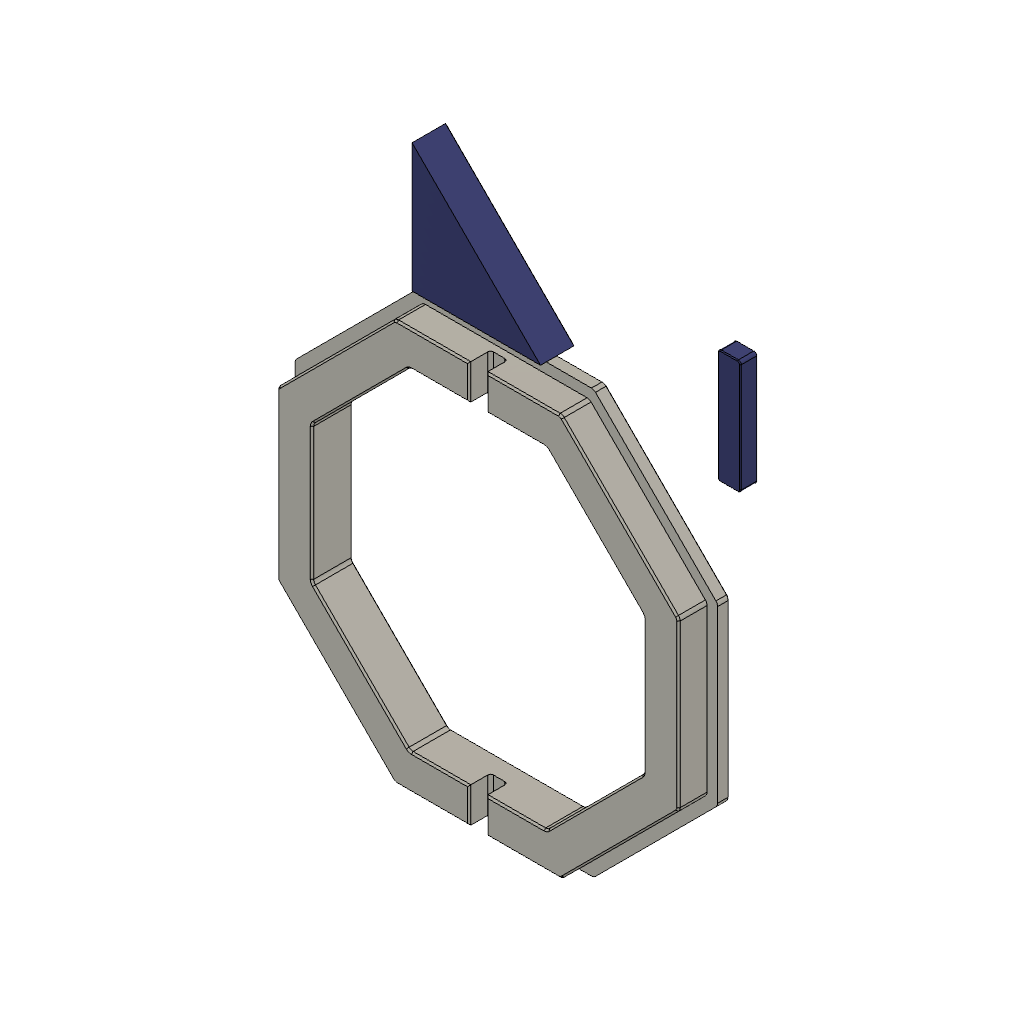
load-test-fixtures (Autodesk Fusion 360 design; units mm, degrees)
part number: 2026-11-02-20-20-52-868
part number: 2026-11-02-20-20-53-079
part number: 2026-11-02-20-20-56-953
part number: 2026-11-02-20-20-59-335
Autodesk Fusion 360 part; units mm, degrees
sketch "Octagonal backer lip" plane through (0, 0, 0) normal (0, 0, 1) x (1, 0, 0) in component "TEST Housing End Backer"
  line L0 (74, 30.6518) -> (30.6518, 74)
  line L1 (30.6518, 74) -> (-30.6518, 74)
  line L2 (-30.6518, 74) -> (-74, 30.6518)
  line L3 (-74, 30.6518) -> (-74, -30.6518)
  line L4 (-74, -30.6518) -> (-30.6518, -74)
  line L5 (-30.6518, -74) -> (30.6518, -74)
  line L6 (30.6518, -74) -> (74, -30.6518)
  line L7 (74, -30.6518) -> (74, 30.6518)
  dimension "d22" = 148
  constraint horizontal L1
  measures "d22" vertical distance of L0.end L5.end
extrude "Four mm recessed stop lip" add sketch "Octagonal backer lip" along normal blind 4 makes body 1 in component "TEST Housing End Backer"
fillet "Backer lip corner radii" radius 2 8 edges at (74, -30.6518, 2) (30.6518, -74, 2) (-30.6518, -74, 2) (-74, -30.6518, 2) (-74, 30.6518, 2) (-30.6518, 74, 2) (30.6518, 74, 2) (74, 30.6518, 2) on bodies 1 in component "TEST Housing End Backer"
ref_plane "WorkPlane1" through (0, 0, 4) normal (0, 0, 1) x (1, 0, 0) in component "TEST Housing End Backer"
sketch "140.6 mm octagonal end-rim pilot" plane through (0, 0, 4) normal (0, 0, 1) x (1, 0, 0) in component "TEST Housing End Backer"
  line L0 (70.3, 29.1192) -> (29.1192, 70.3)
  line L1 (29.1192, 70.3) -> (-29.1192, 70.3)
  line L2 (-29.1192, 70.3) -> (-70.3, 29.1192)
  line L3 (-70.3, 29.1192) -> (-70.3, -29.1192)
  line L4 (-70.3, -29.1192) -> (-29.1192, -70.3)
  line L5 (-29.1192, -70.3) -> (29.1192, -70.3)
  line L6 (29.1192, -70.3) -> (70.3, -29.1192)
  line L7 (70.3, -29.1192) -> (70.3, 29.1192)
  dimension "d29" = 140.6
  constraint horizontal L1
  measures "d29" vertical distance of L0.end L5.end
extrude "Ten mm end-rim support" add sketch "140.6 mm octagonal end-rim pilot" along normal blind 10 bodies 1 in component "TEST Housing End Backer"
fillet "Pilot male corner clearance" radius 2 8 edges at (70.3, -29.1192, 9) (29.1192, -70.3, 9) (-29.1192, -70.3, 9) (-70.3, -29.1192, 9) (-70.3, 29.1192, 9) (-29.1192, 70.3, 9) (29.1192, 70.3, 9) (70.3, 29.1192, 9) on bodies 1 in component "TEST Housing End Backer"
sketch "Octagonal backer opening" plane through (0, 0, 0) normal (0, 0, 1) x (1, 0, 0) in component "TEST Housing End Backer"
  line L0 (58, 24.0244) -> (24.0244, 58)
  line L1 (24.0244, 58) -> (-24.0244, 58)
  line L2 (-24.0244, 58) -> (-58, 24.0244)
  line L3 (-58, 24.0244) -> (-58, -24.0244)
  line L4 (-58, -24.0244) -> (-24.0244, -58)
  line L5 (-24.0244, -58) -> (24.0244, -58)
  line L6 (24.0244, -58) -> (58, -24.0244)
  line L7 (58, -24.0244) -> (58, 24.0244)
  dimension "d34" = 116
  constraint horizontal L1
  measures "d34" vertical distance of L0.end L5.end
extrude "Through access opening" cut sketch "Octagonal backer opening" along normal blind 14 bodies 1 in component "TEST Housing End Backer"
fillet "Backer inner corner radii" radius 2 8 edges at (24.0244, -58, 7) (58, -24.0244, 7) (-24.0244, -58, 7) (-58, -24.0244, 7) (-58, 24.0244, 7) (-24.0244, 58, 7) (24.0244, 58, 7) (58, 24.0244, 7) on bodies 1 in component "TEST Housing End Backer"
sketch "Open cord slots" plane through (0, 0, 0) normal (0, 1, 0) x (1, 0, 0) in component "TEST Housing End Backer"
  line L0 (0, 0) -> (0, -10.75) construction
  line L1 (-3, -15) -> (3, -15)
  line L2 (3, -15) -> (3, -6.5)
  line L3 (3, -6.5) -> (-3, -6.5)
  line L4 (-3, -6.5) -> (-3, -15)
  line L5 (-3, -15) -> (3, -6.5) construction
  dimension "d39" = 10.75
  dimension "d40" = 6
  dimension "d41" = 8.5
  constraint vertical L0
  constraint horizontal L1
  constraint vertical L2
  constraint horizontal L3
  constraint vertical L4
  constraint midpoint L0.end L5
  measures "d39" distance of L0.start L0.end
  measures "d40" distance of L1.start L1.end
  measures "d41" distance of L1.end L2.end
extrude "Both open-ended cord passages" cut sketch "Open cord slots" along normal mid plane 142.6 bodies 1 in component "TEST Housing End Backer"
fillet "Cord slot bottom corner relief" radius 1 4 edges at (3, 64.15, 6.5) (3, -64.15, 6.5) (-3, 64.15, 6.5) (-3, -64.15, 6.5) on bodies 1 in component "TEST Housing End Backer"
chamfer "Backer bed-contact relief" distance 0.3 angle 45 32 edges at (0, -58, 0) (0, 58, 0) (57.8478, 23.9613, 0) (58, 0, 0) (23.9613, 57.8478, 0) (41.0122, 41.0122, 0) (-23.9613, 57.8478, 0) (-57.8478, 23.9613, 0) (-41.0122, 41.0122, 0) (-57.8478, -23.9613, 0) (-58, 0, 0) (-23.9613, -57.8478, 0) (-41.0122, -41.0122, 0) (57.8478, -23.9613, 0) (41.0122, -41.0122, 0) (23.9613, -57.8478, 0) (73.8478, 30.5887, 0) (74, 0, 0) (30.5887, 73.8478, 0) (0, 74, 0) (-30.5887, 73.8478, 0) (-73.8478, 30.5887, 0) (-74, 0, 0) (-73.8478, -30.5887, 0) (-30.5887, -73.8478, 0) (0, -74, 0) (30.5887, -73.8478, 0) (73.8478, -30.5887, 0) (52.3259, -52.3259, 0) (-52.3259, -52.3259, 0) (-52.3259, 52.3259, 0) (52.3259, 52.3259, 0) tangent chain off on bodies 1 in component "TEST Housing End Backer"
chamfer "Backer entry and slot lead-ins" distance 0.6 angle 45 40 edges at (23.9613, 57.8478, 14) (41.0122, 41.0122, 14) (57.8478, 23.9613, 14) (58, 0, 14) (57.8478, -23.9613, 14) (41.0122, -41.0122, 14) (23.9613, -57.8478, 14) (-13.098, -58, 14) (13.098, -58, 14) (-3, -64.15, 14) (-3, 64.15, 14) (3, -64.15, 14) (3, 64.15, 14) (15.6454, -70.3, 14) (29.0562, -70.1478, 14) (49.7096, -49.7096, 14) (70.1478, -29.0562, 14) (70.3, 0, 14) (70.1478, 29.0562, 14) (49.7096, 49.7096, 14) (29.0562, 70.1478, 14) (15.6454, 70.3, 14) (13.098, 58, 14) (-13.098, 58, 14) (-23.9613, 57.8478, 14) (-57.8478, 23.9613, 14) (-41.0122, 41.0122, 14) (-57.8478, -23.9613, 14) (-58, 0, 14) (-23.9613, -57.8478, 14) (-41.0122, -41.0122, 14) (-15.6454, 70.3, 14) (-29.0562, 70.1478, 14) (-49.7096, 49.7096, 14) (-70.1478, 29.0562, 14) (-70.3, 0, 14) (-70.1478, -29.0562, 14) (-49.7096, -49.7096, 14) (-29.0562, -70.1478, 14) (-15.6454, -70.3, 14) tangent chain off on bodies 1 in component "TEST Housing End Backer"
sketch "Equal-leg setup triangle" plane through (0, 0, 0) normal (0, 0, 1) x (1, 0, 0) in component "TEST 45 Degree Setup Block"
  line L0 (0, 0) -> (45, 0)
  line L1 (45, 0) -> (0, 45)
  line L2 (0, 45) -> (0, 0)
  dimension "d48" = 45
  constraint horizontal L0
  constraint vertical L2
  constraint equal L0 L2
  measures "d48" distance of L0.start L0.end
extrude "Twelve mm setup block" add sketch "Equal-leg setup triangle" along normal blind 12 separate body makes body 2 in component "TEST 45 Degree Setup Block"
chamfer "Setup block bed-edge relief" distance 0.3 angle 45 3 edges at (22.5, 22.5, 0) (22.5, 0, 0) (0, 22.5, 0) tangent chain off on bodies 2 in component "TEST 45 Degree Setup Block"
sketch "Clamp shoe footprint" plane through (0, 0, 0) normal (0, 0, 1) x (1, 0, 0) in component "TEST Flat Clamp Shoe"
  line L0 (-4, -20) -> (4, -20)
  line L1 (4, -20) -> (4, 20)
  line L2 (4, 20) -> (-4, 20)
  line L3 (-4, 20) -> (-4, -20)
  line L4 (-4, -20) -> (4, 20) construction
  dimension "d52" = 8
  dimension "d53" = 40
  constraint horizontal L0
  constraint vertical L1
  constraint horizontal L2
  constraint vertical L3
  constraint midpoint origin L4
  measures "d52" distance of L0.start L0.end
  measures "d53" distance of L0.end L1.end
extrude "Six mm clamp shoe" add sketch "Clamp shoe footprint" along normal blind 6 separate body makes body 3 in component "TEST Flat Clamp Shoe"
fillet "Clamp shoe outside corner rounds" radius 1 4 edges at (-4, 20, 3) (4, 20, 3) (4, -20, 3) (-4, -20, 3) on bodies 3 in component "TEST Flat Clamp Shoe"
chamfer "Clamp shoe bed relief" distance 0.3 angle 45 8 edges at (-3.7071, -19.7071, 0) (-4, 0, 0) (3.7071, -19.7071, 0) (4, 0, 0) (3.7071, 19.7071, 0) (-3.7071, 19.7071, 0) (0, 20, 0) (0, -20, 0) tangent chain off on bodies 3 in component "TEST Flat Clamp Shoe"
chamfer "Clamp shoe contact-edge relief" distance 0.3 angle 45 8 edges at (0, 20, 6) (-3.7071, 19.7071, 6) (-4, 0, 6) (-3.7071, -19.7071, 6) (0, -20, 6) (3.7071, -19.7071, 6) (4, 0, 6) (3.7071, 19.7071, 6) tangent chain off on bodies 3 in component "TEST Flat Clamp Shoe"
component "TEST Housing End Backer" placed x (1, 0, 0) y (0, 1, 0) z (0, 0, 1) at (0, 0, 0)
component "TEST 45 Degree Setup Block" placed x (1, 0, 0) y (0, 1, 0) z (0, 0, 1) at (0, 0, 0)
component "TEST Flat Clamp Shoe" placed x (1, 0, 0) y (0, 1, 0) z (0, 0, 1) at (0, 0, 0)
equation "fixtureBedRelief = 0.3 mm" comment "Bed-contact edge relief; do not scale to change fits."
equation "fixtureEntryChamfer = 0.3 mm" comment "Small clearance-hole lead-in."
equation "fixtureBackerLip = 148 mm" comment "Recessed from the 150 mm integrated housing; the jaws contact the end rim."
equation "fixtureBackerLipThickness = 4 mm" comment "End stop; the clamp should grip the housing end band."
equation "fixtureBackerPilot = 140.6 mm" comment "Trial slip fit in the nominal 141 mm integrated end-rim opening."
equation "fixtureBackerDepth = 10 mm" comment "Extends from end X130 to X120, matching the solid end rim."
equation "fixtureBackerOpening = 116 mm" comment "Open center for access and lower material use."
equation "fixtureBackerHeight = fixtureBackerLipThickness + fixtureBackerDepth" comment "Total backer height in print orientation."
equation "fixtureBackerPilotRadius = 2 mm" comment "Male corner relief; verify against actual integrated-rim corner geometry."
equation "fixtureBackerCornerRadius = 2 mm" comment "Lip and inner opening corner radii."
equation "fixtureBackerEntry = 0.6 mm" comment "Pilot entry lead-in."
equation "fixtureCordSlotWidth = 6 mm" comment "Clearance for cord passing through the housing load ports."
equation "fixtureCordSlotFloor = 6.5 mm" comment "Port center is at local Z9; slot remains open through the pilot tip."
equation "fixtureCordSlotHeight = fixtureBackerHeight - fixtureCordSlotFloor + 1 mm" comment "Open-ended slot extends past the pilot tip."
equation "fixtureCordSlotCenter = ( fixtureBackerHeight + 1 mm + fixtureCordSlotFloor ) / 2" comment "Height of the slot sketch center."
equation "fixtureCordSlotRadius = 1 mm" comment "Round the closed slot corners."
equation "fixtureShoeLength = 8 mm" comment "Along body X; contact region X121..129 stays inside the solid end rim."
equation "fixtureShoeWidth = 40 mm" comment "Across the 62.13 mm outer facet, with clearance from the corner rails."
equation "fixtureShoeThickness = 6 mm" comment "Flat load-spreading shoe; add thin grippy lining if the vise needs it."
equation "fixtureSetupLeg = 45 mm" comment "Equal legs establish a 45 degree reference face."
equation "fixtureSetupWidth = 12 mm" comment "Print the triangular face on the bed."
equation "d22 = fixtureBackerLip"
equation "d23 = fixtureBackerLipThickness"
equation "d26 = fixtureBackerCornerRadius"
equation "d27 = fixtureBackerLipThickness"
equation "d29 = fixtureBackerPilot"
equation "d30 = fixtureBackerDepth"
equation "d33 = fixtureBackerPilotRadius"
equation "d34 = fixtureBackerOpening"
equation "d35 = fixtureBackerHeight"
equation "d38 = fixtureBackerCornerRadius"
equation "d39 = fixtureCordSlotCenter"
equation "d40 = fixtureCordSlotWidth"
equation "d41 = fixtureCordSlotHeight"
equation "d42 = fixtureBackerPilot + 2 mm"
equation "d45 = fixtureCordSlotRadius"
equation "d46 = fixtureBedRelief"
equation "d47 = fixtureBackerEntry"
equation "d48 = fixtureSetupLeg"
equation "d49 = fixtureSetupWidth"
equation "d51 = fixtureBedRelief"
equation "d52 = fixtureShoeLength"
equation "d53 = fixtureShoeWidth"
equation "d54 = fixtureShoeThickness"
equation "d58 = fixtureBedRelief"
equation "d59 = fixtureEntryChamfer"
named bodies: "Housing end backer print two", "45 degree setup block print", "Flat clamp shoe print two"
